Thigh_right_knee_interior_part_v5 (Autodesk Fusion 360 design; units mm, degrees)
Autodesk Fusion 360 part; units mm, degrees
sketch "sketch 510" plane through (0, -31.5, 0) normal (0, -1, 0) x (1, 0, 0)
  circle A0 centre (-3.75, -408.5048) radius 1.5
  circle A1 centre (-3.75, -408.5048) radius 1.5
extrude "Extrude1" add sketch "sketch 510" against normal blind 33
sketch "sketch 526" plane through (0, -31.5, 0) normal (0, -1, 0) x (1, 0, 0)
  circle A0 centre (0, -415) radius 4
  circle A1 centre (-3.75, -408.5048) radius 1.5
  circle A2 centre (-3.75, -408.5048) radius 1.5
  circle A3 centre (0, -415) radius 9
extrude "Extrude2" add sketch "sketch 526" against normal blind 31.5
sketch "sketch 547" plane through (0, -31.5, 0) normal (0, -1, 0) x (1, 0, 0)
  circle A0 centre (0, -415) radius 4
  circle A1 centre (-3.75, -408.5048) radius 1.5
  circle A2 centre (-3.75, -408.5048) radius 1.5
  circle A3 centre (0, -415) radius 9
extrude "Extrude3" cut sketch "sketch 547" against normal blind 1.5
chamfer "Chamfer2" distance 1 distance2 5 1 edges at (3.7293, 0, -413.5535) measured on face at (-0.4262, 0, -408.5137) tangent chain off
chamfer "Chamfer3" distance 5 distance2 1 1 edges at (3.7293, -30, -413.5535) measured on face at (-3.9801, -13.3333, -415.3983) tangent chain off
chamfer "Chamfer4" distance 0.5 angle 45 2 edges at (-5.1485, -31.5, -409.0472) (-5.1485, 1.5, -407.9624) tangent chain off
sketch "Sketch1" plane through (0, -30, 0) normal (0, -1, 0) x (1, 0, 0)
  circle A0 centre (-3.75, -408.5048) radius 1.5
  circle A1 centre (0, -415) radius 9
  circle A2 centre (0, -415) radius 5
  circle A3 centre (0, -415) radius 5.25
  circle A4 centre (0, -415) radius 10.3927
  circle A5 centre (0, -415) radius 4.1
  dimension "d1" = 10.5
  dimension "d9" = 8.2
  constraint concentric A1 A3
  constraint concentric A3 A4
  constraint concentric A4 A5
  measures "d1" diameter of A3
  measures "d9" diameter of A5
sketch "Sketch2" plane through (0, 0, 0) normal (0, 1, 0) x (-1, 0, 0)
  circle A0 centre (3.75, -408.5048) radius 1.5
  circle A1 centre (0, -415) radius 9
  circle A2 centre (0, -415) radius 5
  circle A3 centre (0, -415) radius 5.25
  circle A4 centre (0, -415) radius 10.4187
  dimension "d2" = 10.5
  constraint concentric A1 A3
  constraint concentric A3 A4
  measures "d2" diameter of A3
extrude "Extrude4" cut sketch "Sketch2" along normal blind 4 contours A0 | A1 | A4
extrude "Extrude5" cut sketch "Sketch2" against normal blind 4 contours A2 | A3
extrude "Extrude6" cut sketch "Sketch1" against normal blind 4 contours A2 | A3 | A5
extrude "Extrude8" cut sketch "Sketch1" against normal blind 30 contours A5
